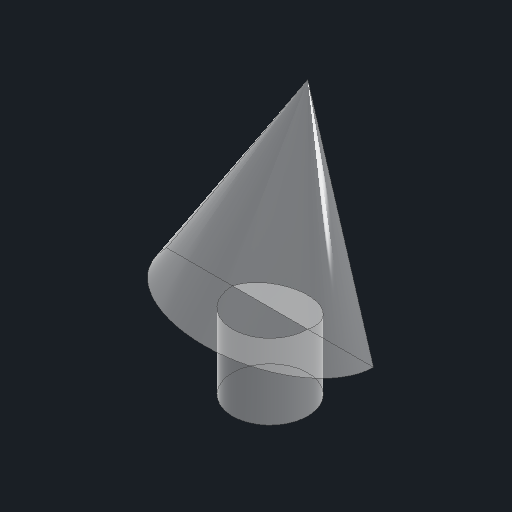
# Autodesk Inventor part: PEN-007
Saved by Autodesk Inventor 2027.1 (Build 311270010, 270A)
## iProperties
Created: 2026-10-28
Part Number: PEN-007
Material: PLA 3D Print
Description: Beak, PLA
Document SubType Name: Modeling
Designer: shyan
Density: 1.24 g/cm^3
Appearance: Polycarbonate - Clear
Mass: 1.43737 g
Surface Area: 8.97764 cm^2
Volume: 1.15917 cm^3
Author: shyan
Autodesk Inventor part; units mm, degrees
ref_plane "sk_beak_base_plane" through (0, 31, 0) normal (0, 1, 0) x (-1, 0, 0)
sketch "sk_beak_base" plane through (0, 31, 0) normal (0, 1, 0) x (-1, 0, 0)
  line L0 (0, 0) -> (40, 0) construction
  line L1 (0, 0) -> (0, 40) construction
  ellipse E0 centre (0, 138) end of major axis (11, 138) minor radius 7
  dimension "d1" = 138
  dimension "d2" = 11
  dimension "d3" = 7
  constraints: 4 end point, 1 centre point, 1 point on line, 5 other
  measures "d1" distance of L0.start E0.centre
ref_plane "Work Plane2" through (0, 50, 0) normal (0, 1, 0) x (-1, 0, 0)
ref_plane "Work Plane3" through (0, 0, 134) normal (0, 0, 1) x (1, 0, 0)
loft "BeakLoft" add profiles "sk_beak_base" section 2 point at (0, 50, 134)
ref_plane "sk_beak_peg_plane" through (0, 31, 0) normal (0, 1, 0) x (-1, 0, 0)
sketch "sk_beak_peg" plane through (0, 31, 0) normal (0, 1, 0) x (-1, 0, 0)
  line L0 (0, 0) -> (40, 0) construction
  line L1 (0, 0) -> (0, 40) construction
  circle A0 centre (0, 138) radius 4
  dimension "d11" = 8
  dimension "d12" = 138
  constraints: 4 end point, 1 centre point, 1 point on line, 4 other
  measures "d11" diameter of A0
  measures "d12" distance of L0.start A0.centre
extrude "BeakPeg" add sketch "sk_beak_peg" against normal blind 8
ref_plane "pl_split" through (0, 31, 138) normal (0, 0.2060105, 0.9785498) x (1, 0, 0)
sketch "sk_trim3" plane through (0, 31, 138) normal (0, 0.2060105, 0.9785498) x (1, 0, 0)
  line L0 (-16, 0) -> (16, 0)
  line L1 (16, 0) -> (16, 30)
  line L2 (16, 30) -> (-16, 30)
  line L3 (-16, 30) -> (-16, 0)
  line L4 (0, 0) -> (50, 0) construction
  line L5 (0, 0) -> (0, 50) construction
  dimension "d17" = 32
  dimension "d18" = 30
  dimension "d19" = -16
  dimension "d20" = 0
  constraints: 12 end point, 2 parallel, 1 horizontal, 1 perpendicular, 4 other
  measures "d17" distance of L0.start L0.end
  measures "d18" distance of L0.end L1.end
  measures "d19" horizontal distance of L4.start L2.end
  measures "d20" vertical distance of L4.start L0.start
extrude "TrimLowerHalf" cut sketch "sk_trim3" against normal through all
equation "\"d1\" = beak_z"
equation "\"d2\" = 0.5 * beak_W"
equation "\"d3\" = 0.5 * beak_H"
equation "\"d11\" = beak_peg_d"
equation "\"d12\" = beak_z"
equation "\"d13\" = beak_peg_L"
equation "\"d17\" = 2 * trim_hw"
equation "\"d18\" = trim_len"
equation "\"d19\" = -trim_hw"
equation "\"clr\" = 0.3"
equation "\"wall\" = 2.4"
equation "\"sv_L\" = 22.8"
equation "\"sv_W\" = 12.2"
equation "\"sv_H\" = 22.7"
equation "\"sv_full\" = 28.5"
equation "\"sv_tab\" = 32.5"
equation "\"sv_tabT\" = 2.5"
equation "\"sv_tabZ\" = 15.5"
equation "\"sv_pitch\" = 27.5"
equation "\"sv_shaft\" = 5.9"
equation "\"sv_dome\" = 12"
equation "\"sv_domeH\" = 3.3"
equation "\"sv_spline\" = 4.8"
equation "\"m2_pilot\" = 1.7"
equation "\"horn_len\" = 31.5"
equation "\"horn_hub\" = 7.2"
equation "\"horn_tip\" = 4.5"
equation "\"horn_T\" = 1.8"
equation "\"horn_hubH\" = 3.8"
equation "\"ins_d\" = 4"
equation "\"ins_L\" = 6"
equation "\"m3\" = 3.4"
equation "\"nut_af\" = 5.8"
equation "\"hip_x\" = 26"
equation "\"plate_T\" = 5"
equation "\"col_H\" = 16"
equation "\"tray_T\" = 3"
equation "\"bodyW0\" = 96"
equation "\"bodyW35\" = 106"
equation "\"bodyD35\" = 86"
equation "\"bodyW85\" = 92"
equation "\"bodyD85\" = 74"
equation "\"bodyW112\" = 64"
equation "\"bodyD112\" = 56"
equation "\"Z_sec1\" = 35"
equation "\"Z_sec2\" = 85"
equation "\"Z_sec3\" = 112"
equation "\"Z_flip\" = 78"
equation "\"Z_bridge\" = 98"
equation "\"bat_W\" = 77"
equation "\"bat_D\" = 41"
equation "\"bat_H\" = 21"
equation "\"esp_W\" = 55"
equation "\"esp_D\" = 28"
equation "\"esp_H\" = 13"
equation "\"pcb_D\" = 38"
equation "\"pcb_T\" = 1.6"
equation "\"bk_D\" = 22"
equation "\"df_W\" = 49"
equation "\"df_D\" = 32"
equation "\"df_H\" = 12"
equation "\"sw_W\" = 21"
equation "\"sw_D\" = 15"
equation "\"sw_H\" = 25"
equation "\"usb_cut_W\" = 12"
equation "\"usb_cut_H\" = 7"
equation "\"usb_pitch\" = 28"
equation "\"beak_W\" = 22"
equation "\"beak_H\" = 14"
equation "\"beak_len\" = 19"
equation "\"beak_y0\" = 31"
equation "\"beak_z\" = 138"
equation "\"beak_peg_d\" = 8"
equation "\"beak_peg_L\" = 8"
equation "\"beak_tip_drop\" = 4"
equation "\"d0\" = beak_y0"
equation "\"d5\" = beak_z - beak_tip_drop"
equation "\"d10\" = beak_y0"
equation "\"trim_hw\" = 16"
equation "\"trim_len\" = 30"
equation "\"trim_back\" = 14"
body "Solid1"
